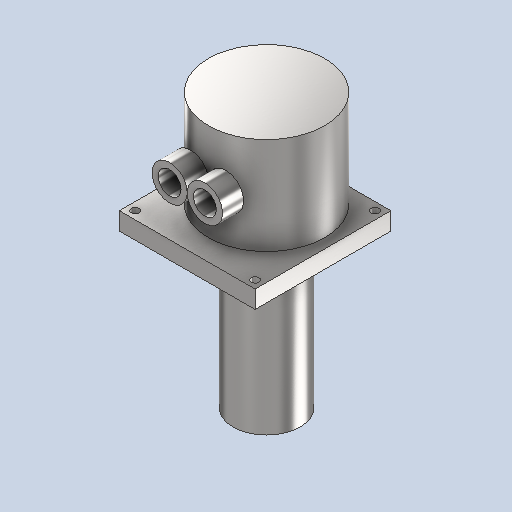
# Autodesk Inventor part: Pompe_model_1.1
Saved by Autodesk Inventor 2025.3 (Build 293356000, 356)
## iProperties
Created: 2025-04-26
Part Number: Pompe_model_1.1
Material: Stahl, galvanisiert
Document SubType Name: Modeling
Designer: karle
Density: 7.85 g/cm^3
Appearance: Galvanisiert
Author: karle
Autodesk Inventor part; units mm, degrees
ref_plane "YZ Plane" through (0, 0, 0) normal (1, 0, 0) x (0, 1, 0)
ref_plane "XZ Plane" through (0, 0, 0) normal (0, 1, 0) x (-1, 0, 0)
sketch "Skizze1" plane through (0, 0, 0) normal (0, 0, 1) x (1, 0, 0)
  circle A0 centre (0, 0) radius 19
  dimension "d0" = 38
  constraints: 1 centre point, 1 coincident
  measures "d0" diameter of A0
extrude "Extrusion1" add sketch "Skizze1" along normal blind 90
sketch "Skizze2" plane through (0, 0, 90) normal (0, 0, 1) x (1, 0, 0)
  line L0 (-38.5, 32) -> (38.5, 32)
  line L1 (38.5, 32) -> (38.5, -45)
  line L2 (38.5, -45) -> (-38.5, -45)
  line L3 (-38.5, -45) -> (-38.5, 32)
  point P0 (0, 0)
  point P1 (-38.5, -6.5)
  dimension "d3" = 77
  dimension "d4" = 77
  dimension "d5" = 38.5
  dimension "d6" = 32
  constraints: 8 end point, 2 parallel, 1 horizontal, 1 midpoint, 1 perpendicular
  measures "d3" distance between parallel lines of L3 L1
  measures "d4" distance between parallel lines of L2 L0
  measures "d5" horizontal distance of point (-38.5, -6.5) point (0, 0)
  measures "d6" distance from line of L0 point (0, 0)
extrude "Extrusion2" add sketch "Skizze2" along normal blind 10
sketch "Skizze3" plane through (0, 0, 100) normal (0, 0, 1) x (1, 0, 0)
  circle A0 centre (0, 0) radius 19 projected
  circle A1 centre (0, 0) radius 33
  dimension "d9" = 66
  constraints: 1 centre point, 1 coincident
  measures "d9" diameter of A1
extrude "Extrusion3" add sketch "Skizze3" along normal blind 55 contours A0 | A1
ref_plane "Arbeitsebene1" through (-38.5, -33, 90) normal (0, -1, 0) x (1, 0, 0)
sketch "Skizze4" plane through (-38.5, -33, 90) normal (0, -1, 0) x (1, 0, 0)
  circle A0 centre (28.5, 38) radius 10
  circle A1 centre (48.5, 38) radius 10
  line L0 (38.5, -90) -> (38.5, 69.9701)
  line L1 (0, 10) -> (77, 10) projected
  circle A2 centre (28.5, 38) radius 6.5
  circle A3 centre (48.5, 38) radius 6.5
  point P0 (38.5, 38)
  dimension "d13" = 20
  dimension "d14" = 20
  dimension "d15" = 28
  dimension "d16" = 13
  constraints: 4 centre point, 3 equal radius, 2 coincident, 2 end point, 1 horizontal alignment, 1 vertical
  measures "d13" diameter of A0
  measures "d14" diameter of A0.centre L0
  measures "d15" distance from line of L1 A1.centre
  measures "d16" diameter of A3
extrude "Extrusion4" add sketch "Skizze4" along normal blind 12
sketch "Skizze5" plane through (0, 0, 100) normal (0, 0, 1) x (1, 0, 0)
  line L0 (-38.5, 32) -> (-38.5, -45) projected
  line L1 (-38.5, -45) -> (38.5, -45) projected
  point P0 (0, 0)
  point P1 (-34, 27.5)
  point P2 (34, 27.5)
  point P3 (34, -40.5)
  point P4 (-34, -40.5)
  dimension "d19" = 68
  dimension "d20" = 4.5
  dimension "d21" = 68
  dimension "d22" = 4.5
  constraints: 2 horizontal alignment, 2 vertical alignment
  measures "d19" distance of point (34, 27.5) point (-34, 27.5)
  measures "d20" distance from line of L0 point (-34, 27.5)
  measures "d21" distance of point (-34, -40.5) point (-34, 27.5)
  measures "d22" distance from line of L1 point (-34, -40.5)
hole "Bohrung1" at (-34, 27.5, 100) at (34, 27.5, 100) at (34, -40.5, 100) at (-34, -40.5, 100) direction (0, 0, -1) diameter 4.5 end through all
